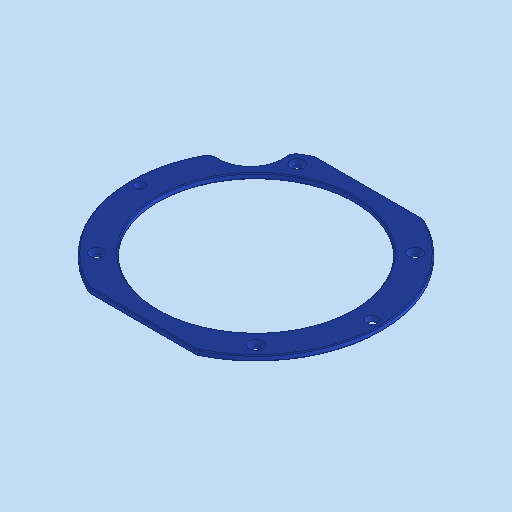
# Autodesk Inventor part: MM0948AN100_G01_191
Saved by Autodesk Inventor 2023.3 (Build 273359000, 359)
## iProperties
Created: 2023-12-11
Part Number: MM0948AN100_G01_191
Material: 3.3547 AlMg4,5Mn0,7 - AW 5083
Description: =<RBPARTNOTITLE2>
Document SubType Name: Modeling
Designer: SFO3AN
Mass: 37.8887 g
Surface Area: 117.181 cm^2
Volume: 14.2439 cm^3
Density: 2.66 g/cm^3
Appearance: blau AnP
RBPARTMADEOF: 3 x 128 x 135 (FM)
RBDRAWINGMISSINGSPEC: --
AnP_Kategorie: 1
RBPARTNOTITLE2: Anfertigungsteil
RBSURFACE: anodised blue
RBPARTNOTITLE1: manufactured part
RBSURFACE2: eloxiert blau
AnP_Material: =<Material>
RBMATERIAL: =<Material>
RBMATNO: =<Part Number>
RBPARTNO: SIEHE MNR
MaxAbmaße: 3 x 128 x 135 (FM)
Author: SFO3AN
Keywords: =<RBPARTMADEOF>
Comments: =<RBSURFACE2>
Revision Number: 01
Autodesk Inventor part; units mm, degrees
ref_plane "YZ Plane" through (0, 0, 0) normal (1, 0, 0) x (0, 1, 0)
ref_plane "XZ Plane" through (0, 0, 0) normal (0, 1, 0) x (-1, 0, 0)
ref_plane "XY Plane" through (0, 0, 0) normal (0, 0, 1) x (1, 0, 0)
sketch "Skizze2" plane through (0, 0, 0) normal (0, 0, 1) x (1, 0, 0)
  line L0 (-94.5, 0) -> (94.5, 0) construction
  line L1 (0, -94.5) -> (0, 94.5) construction
  circle A0 centre (0, 0) radius 67.5
  circle A1 centre (0, 0) radius 52.5
  dimension "d0" = 135
  dimension "d1" = 105
  constraints: 2 centre point, 2 coincident
  measures "d0" diameter of A0
  measures "d1" diameter of A1
extrude "Extrusion1" add sketch "Skizze2" along normal blind 3
sketch "Skizze3" plane through (0, 0, 3) normal (0, 0, 1) x (1, 0, 0)
  line L0 (-94.5, 0) -> (94.5, 0) construction
  line L1 (0, -94.5) -> (0, 94.5) construction
  circle A0 centre (0, 0) radius 60.5 construction
  line L2 (-42.78, -42.78) -> (0, 0) construction
  line L3 (0, 0) -> (42.78, -42.78) construction
  line L4 (0, 0) -> (42.78, 42.78) construction
  line L5 (0, 0) -> (-30.25, 52.3945) construction
  dimension "d4" = 121
  dimension "d5" = 45
  dimension "d6" = 90
  dimension "d7" = 90
  dimension "d8" = 75
  constraints: 8 end point, 4 point on circle, 1 centre point, 1 coincident
  measures "d4" diameter of A0
  measures "d5" angle of L1 L2
  measures "d6" angle of L3 L2
  measures "d7" angle of L3 L4
  measures "d8" angle of L4 L5
hole "Bohrung1" at (-30.25, 52.3945, 3) at (42.78, 42.78, 3) at (42.78, -42.78, 3) at (-42.78, -42.78, 3) direction (0, 0, -1) diameter 3.4 end through all countersink diameter 7.2 countersink angle 90 clearance for "Innensechskant-Senkkopfschraube ISO 10642" size "M3" standard "ISO"
sketch "Skizze4" plane through (0, 0, 3) normal (0, 0, 1) x (1, 0, 0)
  circle A0 centre (-54, 51) radius 17
  line L0 (-98.7, 0) -> (95.2, 0) construction
  line L1 (0, -94.6) -> (0, 95.1) construction
  point P0 (0, 0)
  dimension "d16" = 34
  dimension "d17" = 51
  dimension "d18" = 54
  constraints: 1 centre point
  measures "d16" diameter of A0
  measures "d17" distance from line of L0 A0.centre
  measures "d18" distance from line of L1 A0.centre
extrude "Extrusion2" cut sketch "Skizze4" against normal through all
sketch "Skizze5" plane through (0, 0, 3) normal (0, 0, 1) x (1, 0, 0)
  arc A0 (-58.0269, 34.4838) -> (-37.7407, 55.9633) centre (0, 0) ccw projected
  line L0 (-28.9007, 61) -> (28.9007, 61)
  line L1 (-132.1611, 0) -> (133.3507, 0) construction
  line L2 (0, -133.364) -> (0, 132.2404) construction
  dimension "d21" = 61
  constraints: 2 end point, 2 point on circle, 1 horizontal
  measures "d21" distance between parallel lines of L1 L0
extrude "Extrusion3" cut sketch "Skizze5" against normal through all
fillet "Rundung1" radius 5 2 edges at (28.9007, 61, 1.5) (-28.9007, 61, 1.5)
mirror "Spiegeln1" about plane through (0, 0, 0) normal (0, 1, 0) of "Extrusion3", "Rundung1"
fillet "Rundung2" radius 5 2 edges at (-58.0269, 34.4838, 1.5) (-37.7407, 55.9633, 1.5)
chamfer "Fase1" distance 0.5 angle 45 14 edges at (-41.6408, 39.3274, 3) (-32.3758, 59.2289, 3) (67.5, 0, 3) (-28.8936, 60.8683, 3) (28.8936, 60.8683, 3) (0, 61, 3) (-52.5, 0, 3) (-52.5, 0, 0) (-32.3758, 59.2289, 0) (67.5, 0, 0) (-28.8936, 60.8683, 0) (28.8936, 60.8683, 0) (0, 61, 0) (-41.6408, 39.3274, 0)
sketch "Skizze6" plane through (0, 0, 3) normal (0, 0, 1) x (1, 0, 0)
  line L0 (-94.5, 0) -> (94.5, 0) construction
  line L1 (0, -94.5) -> (0, 94.5) construction
  point P0 (0, 0)
  point P1 (-62.5, 0)
  dimension "d29" = 62.5
  constraints: 1 point on line
  measures "d29" distance from line of L1 point (-62.5, 0)
hole "Bohrung2" at (-62.5, 0, 3) direction (0, 0, -1) diameter 5.1 end through all
sketch "Skizze7" plane through (0, 0, 3) normal (0, 0, 1) x (1, 0, 0)
  line L0 (-94.5, 0) -> (94.5, 0) construction
  line L1 (0, -94.5) -> (0, 94.5) construction
  circle A0 centre (-62.5, 0) radius 2.55 projected
  point P0 (0, 0)
  point P1 (62.5, 0)
  dimension "d37" = 62.5
  constraints: 1 point on line, 1 symmetric about line
  measures "d37" distance from line of A0.centre L1
hole "Bohrung3" at (62.5, 0, 3) direction (0, 0, -1) diameter 6.1 end through all
